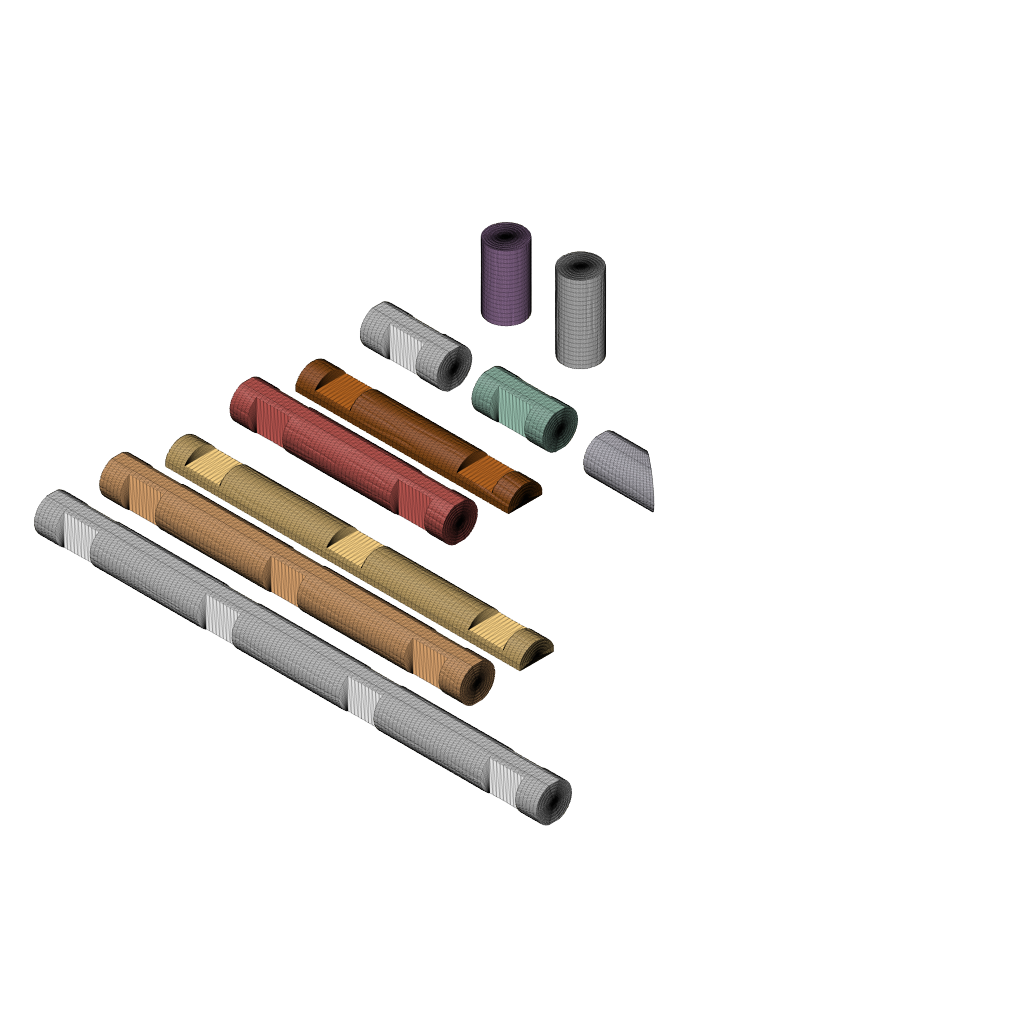
DeadPresidentTreeSections_flat_end_round (Autodesk Fusion 360 design; units mm, degrees)
part number: 2026-11-17-20-52-56-390
part number: 2026-11-17-20-52-56-571
part number: 2026-11-17-20-52-56-825
part number: 2026-11-17-20-52-57-040
part number: 2026-11-17-20-52-57-312
part number: 2026-11-17-20-52-57-710
part number: 2026-11-17-20-52-58-071
part number: 2026-11-17-20-52-58-452
part number: 2026-11-17-20-52-58-901
part number: 2026-11-17-20-52-59-269
part number: 2026-11-17-20-52-59-409
Autodesk Fusion 360 part; units mm, degrees
sketch "Section" plane through (0, 0, 0) normal (1, 0, 0) x (0, 0, -1) in component "log_1insert_1-5_8"
  circle A0 centre (-9.125, 0) radius 9.525
  dimension "d14" = 9.125
  dimension "d15" = 19.05
  constraint horizontal origin A0.centre
  measures "d14" horizontal distance of origin A0.centre
  measures "d15" diameter of A0
extrude "Log" add sketch "Section" along normal blind 41.275 makes body 1 in component "log_1insert_1-5_8"
sketch "Flats" plane through (0, 0, 0) normal (1, 0, 0) x (0, 0, -1) in component "log_1insert_1-5_8"
  line L0 (0.8, -11.525) -> (0.8, 11.525)
  line L1 (0.8, 11.525) -> (0, 11.525)
  line L2 (0, 11.525) -> (0, -11.525)
  line L3 (0, -11.525) -> (0.8, -11.525)
  line L4 (-18.25, -11.525) -> (-18.25, 11.525)
  line L5 (-18.25, 11.525) -> (-20.05, 11.525)
  line L6 (-20.05, 11.525) -> (-20.05, -11.525)
  line L7 (-20.05, -11.525) -> (-18.25, -11.525)
  dimension "d18" = 11.525
  dimension "d19" = 0.8
  dimension "d20" = 11.525
  dimension "d21" = 11.525
  dimension "d22" = 18.25
  dimension "d23" = 11.525
  dimension "d24" = 20.05
  constraint vertical L0
  constraint horizontal L1
  constraint vertical L2
  constraint horizontal L3
  constraint vertical origin L1.end
  constraint vertical L4
  constraint horizontal L5
  constraint vertical L6
  constraint horizontal L7
  measures "d18" vertical distance of origin L0.start
  measures "d19" horizontal distance of origin L0.start
  measures "d20" vertical distance of origin L1.end
  measures "d21" vertical distance of origin L4.start
  measures "d22" horizontal distance of origin L4.start
  measures "d23" vertical distance of origin L5.end
  measures "d24" horizontal distance of origin L5.end
extrude "Flats (1)" cut sketch "Flats" along normal blind 41.275 bodies 1 in component "log_1insert_1-5_8"
sketch "Notch" plane through (0, 0, 0) normal (0, 0, 1) x (1, 0, 0) in component "log_1insert_1-5_8"
  line L0 (11.3125, 4.7625) -> (29.9625, 4.7625)
  line L1 (29.9625, 4.7625) -> (29.9625, 11.525)
  line L2 (29.9625, 11.525) -> (11.3125, 11.525)
  line L3 (11.3125, 11.525) -> (11.3125, 4.7625)
  line L4 (11.3125, -4.7625) -> (29.9625, -4.7625)
  line L5 (29.9625, -4.7625) -> (29.9625, -11.525)
  line L6 (29.9625, -11.525) -> (11.3125, -11.525)
  line L7 (11.3125, -11.525) -> (11.3125, -4.7625)
  dimension "d27" = 11.3125
  dimension "d28" = 4.7625
  dimension "d29" = 29.9625
  dimension "d30" = 11.525
  dimension "d31" = 11.3125
  dimension "d32" = 4.7625
  dimension "d33" = 29.9625
  dimension "d34" = 11.525
  constraint horizontal L0
  constraint vertical L1
  constraint horizontal L2
  constraint vertical L3
  constraint horizontal L4
  constraint vertical L5
  constraint horizontal L6
  constraint vertical L7
  measures "d27" horizontal distance of origin L0.start
  measures "d28" vertical distance of origin L0.start
  measures "d29" horizontal distance of origin L1.end
  measures "d30" vertical distance of origin L1.end
  measures "d31" horizontal distance of origin L4.start
  measures "d32" vertical distance of origin L4.start
  measures "d33" horizontal distance of origin L5.end
  measures "d34" vertical distance of origin L5.end
extrude "Notch cut" cut sketch "Notch" along normal blind 21.05 bodies 1 in component "log_1insert_1-5_8"
pattern_linear "Notch pattern" count 2 spacing 0.001 along (1, 0, 0) count 3 spacing 0 along (1, 0, 0) of "Notch cut" in component "log_1insert_1-5_8"
other "Base Mesh Feature1" in component "log_1insert_1-5_8"
sketch "Section (2)" plane through (0, 0, 0) normal (1, 0, 0) x (0, 0, -1) in component "log_1insert_1-1_2_round"
  circle A0 centre (-9.125, 0) radius 9.525
  dimension "d45" = 9.125
  dimension "d46" = 19.05
  constraint horizontal origin A0.centre
  measures "d45" horizontal distance of origin A0.centre
  measures "d46" diameter of A0
extrude "Log'" add sketch "Section (2)" along normal blind 38.1 separate body makes body 2 in component "log_1insert_1-1_2_round"
sketch "Flats (2)" plane through (0, 0, 0) normal (1, 0, 0) x (0, 0, -1) in component "log_1insert_1-1_2_round"
  line L0 (0.8, -11.525) -> (0.8, 11.525)
  line L1 (0.8, 11.525) -> (0, 11.525)
  line L2 (0, 11.525) -> (0, -11.525)
  line L3 (0, -11.525) -> (0.8, -11.525)
  line L4 (-18.25, -11.525) -> (-18.25, 11.525)
  line L5 (-18.25, 11.525) -> (-20.05, 11.525)
  line L6 (-20.05, 11.525) -> (-20.05, -11.525)
  line L7 (-20.05, -11.525) -> (-18.25, -11.525)
  dimension "d49" = 11.525
  dimension "d50" = 0.8
  dimension "d51" = 11.525
  dimension "d52" = 11.525
  dimension "d53" = 18.25
  dimension "d54" = 11.525
  dimension "d55" = 20.05
  constraint vertical L0
  constraint horizontal L1
  constraint vertical L2
  constraint horizontal L3
  constraint vertical origin L1.end
  constraint vertical L4
  constraint horizontal L5
  constraint vertical L6
  constraint horizontal L7
  measures "d49" vertical distance of origin L0.start
  measures "d50" horizontal distance of origin L0.start
  measures "d51" vertical distance of origin L1.end
  measures "d52" vertical distance of origin L4.start
  measures "d53" horizontal distance of origin L4.start
  measures "d54" vertical distance of origin L5.end
  measures "d55" horizontal distance of origin L5.end
extrude "Flats (1)'" cut sketch "Flats (2)" along normal blind 38.1 bodies 2 in component "log_1insert_1-1_2_round"
sketch "Notch (2)" plane through (0, 0, 0) normal (0, 0, 1) x (1, 0, 0) in component "log_1insert_1-1_2_round"
  line L0 (9.725, 4.7625) -> (28.375, 4.7625)
  line L1 (28.375, 4.7625) -> (28.375, 11.525)
  line L2 (28.375, 11.525) -> (9.725, 11.525)
  line L3 (9.725, 11.525) -> (9.725, 4.7625)
  line L4 (9.725, -4.7625) -> (28.375, -4.7625)
  line L5 (28.375, -4.7625) -> (28.375, -11.525)
  line L6 (28.375, -11.525) -> (9.725, -11.525)
  line L7 (9.725, -11.525) -> (9.725, -4.7625)
  dimension "d58" = 9.725
  dimension "d59" = 4.7625
  dimension "d60" = 28.375
  dimension "d61" = 11.525
  dimension "d62" = 9.725
  dimension "d63" = 4.7625
  dimension "d64" = 28.375
  dimension "d65" = 11.525
  constraint horizontal L0
  constraint vertical L1
  constraint horizontal L2
  constraint vertical L3
  constraint horizontal L4
  constraint vertical L5
  constraint horizontal L6
  constraint vertical L7
  measures "d58" horizontal distance of origin L0.start
  measures "d59" vertical distance of origin L0.start
  measures "d60" horizontal distance of origin L1.end
  measures "d61" vertical distance of origin L1.end
  measures "d62" horizontal distance of origin L4.start
  measures "d63" vertical distance of origin L4.start
  measures "d64" horizontal distance of origin L5.end
  measures "d65" vertical distance of origin L5.end
extrude "Notch cut'" cut sketch "Notch (2)" along normal blind 21.05 bodies 2 in component "log_1insert_1-1_2_round"
pattern_linear "Notch pattern'" count 2 spacing 0.001 along (1, 0, 0) count 3 spacing 0 along (1, 0, 0) of "Notch cut'" in component "log_1insert_1-1_2_round"
other "Base Mesh Feature1'" in component "log_1insert_1-1_2_round"
sketch "Section (3)" plane through (0, 0, 0) normal (1, 0, 0) x (0, 0, -1) in component "log_2insert_4-1_2"
  circle A0 centre (-9.125, 0) radius 9.525
  dimension "d76" = 9.125
  dimension "d77" = 19.05
  constraint horizontal origin A0.centre
  measures "d76" horizontal distance of origin A0.centre
  measures "d77" diameter of A0
extrude "Log''" add sketch "Section (3)" along normal blind 114.3 separate body makes body 3 in component "log_2insert_4-1_2"
sketch "Flats (3)" plane through (0, 0, 0) normal (1, 0, 0) x (0, 0, -1) in component "log_2insert_4-1_2"
  line L0 (0.8, -11.525) -> (0.8, 11.525)
  line L1 (0.8, 11.525) -> (0, 11.525)
  line L2 (0, 11.525) -> (0, -11.525)
  line L3 (0, -11.525) -> (0.8, -11.525)
  line L4 (-18.25, -11.525) -> (-18.25, 11.525)
  line L5 (-18.25, 11.525) -> (-20.05, 11.525)
  line L6 (-20.05, 11.525) -> (-20.05, -11.525)
  line L7 (-20.05, -11.525) -> (-18.25, -11.525)
  dimension "d80" = 11.525
  dimension "d81" = 0.8
  dimension "d82" = 11.525
  dimension "d83" = 11.525
  dimension "d84" = 18.25
  dimension "d85" = 11.525
  dimension "d86" = 20.05
  constraint vertical L0
  constraint horizontal L1
  constraint vertical L2
  constraint horizontal L3
  constraint vertical origin L1.end
  constraint vertical L4
  constraint horizontal L5
  constraint vertical L6
  constraint horizontal L7
  measures "d80" vertical distance of origin L0.start
  measures "d81" horizontal distance of origin L0.start
  measures "d82" vertical distance of origin L1.end
  measures "d83" vertical distance of origin L4.start
  measures "d84" horizontal distance of origin L4.start
  measures "d85" vertical distance of origin L5.end
  measures "d86" horizontal distance of origin L5.end
extrude "Flats (1)''" cut sketch "Flats (3)" along normal blind 114.3 bodies 3 in component "log_2insert_4-1_2"
sketch "Notch (3)" plane through (0, 0, 0) normal (0, 0, 1) x (1, 0, 0) in component "log_2insert_4-1_2"
  line L0 (9.725, 4.7625) -> (28.375, 4.7625)
  line L1 (28.375, 4.7625) -> (28.375, 11.525)
  line L2 (28.375, 11.525) -> (9.725, 11.525)
  line L3 (9.725, 11.525) -> (9.725, 4.7625)
  line L4 (9.725, -4.7625) -> (28.375, -4.7625)
  line L5 (28.375, -4.7625) -> (28.375, -11.525)
  line L6 (28.375, -11.525) -> (9.725, -11.525)
  line L7 (9.725, -11.525) -> (9.725, -4.7625)
  dimension "d89" = 9.725
  dimension "d90" = 4.7625
  dimension "d91" = 28.375
  dimension "d92" = 11.525
  dimension "d93" = 9.725
  dimension "d94" = 4.7625
  dimension "d95" = 28.375
  dimension "d96" = 11.525
  constraint horizontal L0
  constraint vertical L1
  constraint horizontal L2
  constraint vertical L3
  constraint horizontal L4
  constraint vertical L5
  constraint horizontal L6
  constraint vertical L7
  measures "d89" horizontal distance of origin L0.start
  measures "d90" vertical distance of origin L0.start
  measures "d91" horizontal distance of origin L1.end
  measures "d92" vertical distance of origin L1.end
  measures "d93" horizontal distance of origin L4.start
  measures "d94" vertical distance of origin L4.start
  measures "d95" horizontal distance of origin L5.end
  measures "d96" vertical distance of origin L5.end
extrude "Notch cut''" cut sketch "Notch (3)" along normal blind 21.05 bodies 3 in component "log_2insert_4-1_2"
pattern_linear "Notch pattern''" count 2 spacing 76.2 along (1, 0, 0) count 3 spacing 0 along (1, 0, 0) of "Notch cut''" in component "log_2insert_4-1_2"
other "Base Mesh Feature1''" in component "log_2insert_4-1_2"
sketch "Section (4)" plane through (0, 0, 0) normal (1, 0, 0) x (0, 0, -1) in component "log_3insert_7-5_8"
  circle A0 centre (-9.125, 0) radius 9.525
  dimension "d107" = 9.125
  dimension "d108" = 19.05
  constraint horizontal origin A0.centre
  measures "d107" horizontal distance of origin A0.centre
  measures "d108" diameter of A0
extrude "Log'''" add sketch "Section (4)" along normal blind 193.675 separate body makes body 4 in component "log_3insert_7-5_8"
sketch "Flats (4)" plane through (0, 0, 0) normal (1, 0, 0) x (0, 0, -1) in component "log_3insert_7-5_8"
  line L0 (0.8, -11.525) -> (0.8, 11.525)
  line L1 (0.8, 11.525) -> (0, 11.525)
  line L2 (0, 11.525) -> (0, -11.525)
  line L3 (0, -11.525) -> (0.8, -11.525)
  line L4 (-18.25, -11.525) -> (-18.25, 11.525)
  line L5 (-18.25, 11.525) -> (-20.05, 11.525)
  line L6 (-20.05, 11.525) -> (-20.05, -11.525)
  line L7 (-20.05, -11.525) -> (-18.25, -11.525)
  dimension "d111" = 11.525
  dimension "d112" = 0.8
  dimension "d113" = 11.525
  dimension "d114" = 11.525
  dimension "d115" = 18.25
  dimension "d116" = 11.525
  dimension "d117" = 20.05
  constraint vertical L0
  constraint horizontal L1
  constraint vertical L2
  constraint horizontal L3
  constraint vertical origin L1.end
  constraint vertical L4
  constraint horizontal L5
  constraint vertical L6
  constraint horizontal L7
  measures "d111" vertical distance of origin L0.start
  measures "d112" horizontal distance of origin L0.start
  measures "d113" vertical distance of origin L1.end
  measures "d114" vertical distance of origin L4.start
  measures "d115" horizontal distance of origin L4.start
  measures "d116" vertical distance of origin L5.end
  measures "d117" horizontal distance of origin L5.end
extrude "Flats (1)'''" cut sketch "Flats (4)" along normal blind 193.675 bodies 4 in component "log_3insert_7-5_8"
sketch "Notch (4)" plane through (0, 0, 0) normal (0, 0, 1) x (1, 0, 0) in component "log_3insert_7-5_8"
  line L0 (11.3125, 4.7625) -> (29.9625, 4.7625)
  line L1 (29.9625, 4.7625) -> (29.9625, 11.525)
  line L2 (29.9625, 11.525) -> (11.3125, 11.525)
  line L3 (11.3125, 11.525) -> (11.3125, 4.7625)
  line L4 (11.3125, -4.7625) -> (29.9625, -4.7625)
  line L5 (29.9625, -4.7625) -> (29.9625, -11.525)
  line L6 (29.9625, -11.525) -> (11.3125, -11.525)
  line L7 (11.3125, -11.525) -> (11.3125, -4.7625)
  dimension "d120" = 11.3125
  dimension "d121" = 4.7625
  dimension "d122" = 29.9625
  dimension "d123" = 11.525
  dimension "d124" = 11.3125
  dimension "d125" = 4.7625
  dimension "d126" = 29.9625
  dimension "d127" = 11.525
  constraint horizontal L0
  constraint vertical L1
  constraint horizontal L2
  constraint vertical L3
  constraint horizontal L4
  constraint vertical L5
  constraint horizontal L6
  constraint vertical L7
  measures "d120" horizontal distance of origin L0.start
  measures "d121" vertical distance of origin L0.start
  measures "d122" horizontal distance of origin L1.end
  measures "d123" vertical distance of origin L1.end
  measures "d124" horizontal distance of origin L4.start
  measures "d125" vertical distance of origin L4.start
  measures "d126" horizontal distance of origin L5.end
  measures "d127" vertical distance of origin L5.end
extrude "Notch cut'''" cut sketch "Notch (4)" along normal blind 21.05 bodies 4 in component "log_3insert_7-5_8"
pattern_linear "Notch pattern'''" count 3 spacing 76.2 along (1, 0, 0) count 3 spacing 0 along (1, 0, 0) of "Notch cut'''" in component "log_3insert_7-5_8"
other "Base Mesh Feature1'''" in component "log_3insert_7-5_8"
sketch "Section (5)" plane through (0, 0, 0) normal (1, 0, 0) x (0, 0, -1) in component "log_4insert_10-5_8"
  circle A0 centre (-9.125, 0) radius 9.525
  dimension "d138" = 9.125
  dimension "d139" = 19.05
  constraint horizontal origin A0.centre
  measures "d138" horizontal distance of origin A0.centre
  measures "d139" diameter of A0
extrude "Log''''" add sketch "Section (5)" along normal blind 269.875 separate body makes body 5 in component "log_4insert_10-5_8"
sketch "Flats (5)" plane through (0, 0, 0) normal (1, 0, 0) x (0, 0, -1) in component "log_4insert_10-5_8"
  line L0 (0.8, -11.525) -> (0.8, 11.525)
  line L1 (0.8, 11.525) -> (0, 11.525)
  line L2 (0, 11.525) -> (0, -11.525)
  line L3 (0, -11.525) -> (0.8, -11.525)
  line L4 (-18.25, -11.525) -> (-18.25, 11.525)
  line L5 (-18.25, 11.525) -> (-20.05, 11.525)
  line L6 (-20.05, 11.525) -> (-20.05, -11.525)
  line L7 (-20.05, -11.525) -> (-18.25, -11.525)
  dimension "d142" = 11.525
  dimension "d143" = 0.8
  dimension "d144" = 11.525
  dimension "d145" = 11.525
  dimension "d146" = 18.25
  dimension "d147" = 11.525
  dimension "d148" = 20.05
  constraint vertical L0
  constraint horizontal L1
  constraint vertical L2
  constraint horizontal L3
  constraint vertical origin L1.end
  constraint vertical L4
  constraint horizontal L5
  constraint vertical L6
  constraint horizontal L7
  measures "d142" vertical distance of origin L0.start
  measures "d143" horizontal distance of origin L0.start
  measures "d144" vertical distance of origin L1.end
  measures "d145" vertical distance of origin L4.start
  measures "d146" horizontal distance of origin L4.start
  measures "d147" vertical distance of origin L5.end
  measures "d148" horizontal distance of origin L5.end
extrude "Flats (1)''''" cut sketch "Flats (5)" along normal blind 269.875 bodies 5 in component "log_4insert_10-5_8"
sketch "Notch (5)" plane through (0, 0, 0) normal (0, 0, 1) x (1, 0, 0) in component "log_4insert_10-5_8"
  line L0 (11.3125, 4.7625) -> (29.9625, 4.7625)
  line L1 (29.9625, 4.7625) -> (29.9625, 11.525)
  line L2 (29.9625, 11.525) -> (11.3125, 11.525)
  line L3 (11.3125, 11.525) -> (11.3125, 4.7625)
  line L4 (11.3125, -4.7625) -> (29.9625, -4.7625)
  line L5 (29.9625, -4.7625) -> (29.9625, -11.525)
  line L6 (29.9625, -11.525) -> (11.3125, -11.525)
  line L7 (11.3125, -11.525) -> (11.3125, -4.7625)
  dimension "d151" = 11.3125
  dimension "d152" = 4.7625
  dimension "d153" = 29.9625
  dimension "d154" = 11.525
  dimension "d155" = 11.3125
  dimension "d156" = 4.7625
  dimension "d157" = 29.9625
  dimension "d158" = 11.525
  constraint horizontal L0
  constraint vertical L1
  constraint horizontal L2
  constraint vertical L3
  constraint horizontal L4
  constraint vertical L5
  constraint horizontal L6
  constraint vertical L7
  measures "d151" horizontal distance of origin L0.start
  measures "d152" vertical distance of origin L0.start
  measures "d153" horizontal distance of origin L1.end
  measures "d154" vertical distance of origin L1.end
  measures "d155" horizontal distance of origin L4.start
  measures "d156" vertical distance of origin L4.start
  measures "d157" horizontal distance of origin L5.end
  measures "d158" vertical distance of origin L5.end
extrude "Notch cut''''" cut sketch "Notch (5)" along normal blind 21.05 bodies 5 in component "log_4insert_10-5_8"
pattern_linear "Notch pattern''''" count 4 spacing 76.2 along (1, 0, 0) count 3 spacing 0 along (1, 0, 0) of "Notch cut''''" in component "log_4insert_10-5_8"
other "Base Mesh Feature1''''" in component "log_4insert_10-5_8"
sketch "Section (6)" plane through (0, 0, 0) normal (1, 0, 0) x (0, 0, -1) in component "base_log_4-1_2"
  circle A0 centre (0, 0) radius 9.525
  dimension "d169" = 19.05
  constraint coincident A0.centre origin
  measures "d169" diameter of A0
extrude "Log'''''" add sketch "Section (6)" along normal blind 114.3 separate body makes body 6 in component "base_log_4-1_2"
sketch "Bed and side flats" plane through (0, 0, 0) normal (1, 0, 0) x (0, 0, -1) in component "base_log_4-1_2"
  line L0 (10.525, -11.525) -> (10.525, 11.525)
  line L1 (10.525, 11.525) -> (0, 11.525)
  line L2 (0, 11.525) -> (0, -11.525)
  line L3 (0, -11.525) -> (10.525, -11.525)
  line L4 (1, 9.125) -> (1, 11.525)
  line L5 (1, 11.525) -> (-20.05, 11.525)
  line L6 (-20.05, 11.525) -> (-20.05, 9.125)
  line L7 (-20.05, 9.125) -> (1, 9.125)
  line L8 (1, -9.125) -> (1, -11.525)
  line L9 (1, -11.525) -> (-20.05, -11.525)
  line L10 (-20.05, -11.525) -> (-20.05, -9.125)
  line L11 (-20.05, -9.125) -> (1, -9.125)
  dimension "d172" = 11.525
  dimension "d173" = 10.525
  dimension "d174" = 11.525
  dimension "d175" = 9.125
  dimension "d176" = 1
  dimension "d177" = 11.525
  dimension "d178" = 20.05
  dimension "d179" = 9.125
  dimension "d180" = 1
  dimension "d181" = 11.525
  dimension "d182" = 20.05
  constraint vertical L0
  constraint horizontal L1
  constraint vertical L2
  constraint horizontal L3
  constraint vertical origin L1.end
  constraint vertical L4
  constraint horizontal L5
  constraint vertical L6
  constraint horizontal L7
  constraint vertical L8
  constraint horizontal L9
  constraint vertical L10
  constraint horizontal L11
  measures "d172" vertical distance of origin L0.start
  measures "d173" horizontal distance of origin L0.start
  measures "d174" vertical distance of origin L1.end
  measures "d175" vertical distance of origin L4.start
  measures "d176" horizontal distance of origin L4.start
  measures "d177" vertical distance of origin L5.end
  measures "d178" horizontal distance of origin L5.end
  measures "d179" vertical distance of origin L8.start
  measures "d180" horizontal distance of origin L8.start
  measures "d181" vertical distance of origin L9.end
  measures "d182" horizontal distance of origin L9.end
extrude "Bed and side flats (1)" cut sketch "Bed and side flats" along normal blind 114.3 bodies 6 in component "base_log_4-1_2"
sketch "Notch (6)" plane through (0, 0, 0) normal (0, 1, 0) x (1, 0, 0) in component "base_log_4-1_2"
  line L0 (9.725, -4.7625) -> (28.375, -4.7625)
  line L1 (28.375, -4.7625) -> (28.375, -10.525)
  line L2 (28.375, -10.525) -> (9.725, -10.525)
  line L3 (9.725, -10.525) -> (9.725, -4.7625)
  dimension "d185" = 9.725
  dimension "d186" = 4.7625
  dimension "d187" = 28.375
  dimension "d188" = 10.525
  constraint horizontal L0
  constraint vertical L1
  constraint horizontal L2
  constraint vertical L3
  measures "d185" horizontal distance of origin L0.start
  measures "d186" vertical distance of origin L0.start
  measures "d187" horizontal distance of origin L1.end
  measures "d188" vertical distance of origin L1.end
extrude "Notch cut'''''" cut sketch "Notch (6)" along normal mid plane 21.05 bodies 6 in component "base_log_4-1_2"
pattern_linear "Notch pattern'''''" count 2 spacing 76.2 along (1, 0, 0) count 3 spacing 0 along (1, 0, 0) of "Notch cut'''''" in component "base_log_4-1_2"
other "Base Mesh Feature1'''''" in component "base_log_4-1_2"
sketch "Section (7)" plane through (0, 0, 0) normal (1, 0, 0) x (0, 0, -1) in component "base_log_7-1_2"
  circle A0 centre (0, 0) radius 9.525
  dimension "d199" = 19.05
  constraint coincident A0.centre origin
  measures "d199" diameter of A0
extrude "Log''''''" add sketch "Section (7)" along normal blind 190.5 separate body makes body 7 in component "base_log_7-1_2"
sketch "Bed and side flats (2)" plane through (0, 0, 0) normal (1, 0, 0) x (0, 0, -1) in component "base_log_7-1_2"
  line L0 (10.525, -11.525) -> (10.525, 11.525)
  line L1 (10.525, 11.525) -> (0, 11.525)
  line L2 (0, 11.525) -> (0, -11.525)
  line L3 (0, -11.525) -> (10.525, -11.525)
  line L4 (1, 9.125) -> (1, 11.525)
  line L5 (1, 11.525) -> (-20.05, 11.525)
  line L6 (-20.05, 11.525) -> (-20.05, 9.125)
  line L7 (-20.05, 9.125) -> (1, 9.125)
  line L8 (1, -9.125) -> (1, -11.525)
  line L9 (1, -11.525) -> (-20.05, -11.525)
  line L10 (-20.05, -11.525) -> (-20.05, -9.125)
  line L11 (-20.05, -9.125) -> (1, -9.125)
  dimension "d202" = 11.525
  dimension "d203" = 10.525
  dimension "d204" = 11.525
  dimension "d205" = 9.125
  dimension "d206" = 1
  dimension "d207" = 11.525
  dimension "d208" = 20.05
  dimension "d209" = 9.125
  dimension "d210" = 1
  dimension "d211" = 11.525
  dimension "d212" = 20.05
  constraint vertical L0
  constraint horizontal L1
  constraint vertical L2
  constraint horizontal L3
  constraint vertical origin L1.end
  constraint vertical L4
  constraint horizontal L5
  constraint vertical L6
  constraint horizontal L7
  constraint vertical L8
  constraint horizontal L9
  constraint vertical L10
  constraint horizontal L11
  measures "d202" vertical distance of origin L0.start
  measures "d203" horizontal distance of origin L0.start
  measures "d204" vertical distance of origin L1.end
  measures "d205" vertical distance of origin L4.start
  measures "d206" horizontal distance of origin L4.start
  measures "d207" vertical distance of origin L5.end
  measures "d208" horizontal distance of origin L5.end
  measures "d209" vertical distance of origin L8.start
  measures "d210" horizontal distance of origin L8.start
  measures "d211" vertical distance of origin L9.end
  measures "d212" horizontal distance of origin L9.end
extrude "Bed and side flats (1)'" cut sketch "Bed and side flats (2)" along normal blind 190.5 bodies 7 in component "base_log_7-1_2"
sketch "Notch (7)" plane through (0, 0, 0) normal (0, 1, 0) x (1, 0, 0) in component "base_log_7-1_2"
  line L0 (9.725, -4.7625) -> (28.375, -4.7625)
  line L1 (28.375, -4.7625) -> (28.375, -10.525)
  line L2 (28.375, -10.525) -> (9.725, -10.525)
  line L3 (9.725, -10.525) -> (9.725, -4.7625)
  dimension "d215" = 9.725
  dimension "d216" = 4.7625
  dimension "d217" = 28.375
  dimension "d218" = 10.525
  constraint horizontal L0
  constraint vertical L1
  constraint horizontal L2
  constraint vertical L3
  measures "d215" horizontal distance of origin L0.start
  measures "d216" vertical distance of origin L0.start
  measures "d217" horizontal distance of origin L1.end
  measures "d218" vertical distance of origin L1.end
extrude "Notch cut''''''" cut sketch "Notch (7)" along normal mid plane 21.05 bodies 7 in component "base_log_7-1_2"
pattern_linear "Notch pattern''''''" count 3 spacing 76.2 along (1, 0, 0) count 3 spacing 0 along (1, 0, 0) of "Notch cut''''''" in component "base_log_7-1_2"
other "Base Mesh Feature1''''''" in component "base_log_7-1_2"
sketch "Section (8)" plane through (0, 0, 0) normal (1, 0, 0) x (0, 0, -1) in component "beveled_end_1-1_2"
  circle A0 centre (-9.125, 0) radius 9.525
  dimension "d227" = 9.125
  dimension "d228" = 19.05
  constraint horizontal origin A0.centre
  measures "d227" horizontal distance of origin A0.centre
  measures "d228" diameter of A0
extrude "Log'''''''" add sketch "Section (8)" along normal blind 38.1 separate body makes body 8 in component "beveled_end_1-1_2"
sketch "Flats (6)" plane through (0, 0, 0) normal (1, 0, 0) x (0, 0, -1) in component "beveled_end_1-1_2"
  line L0 (0.8, -11.525) -> (0.8, 11.525)
  line L1 (0.8, 11.525) -> (0, 11.525)
  line L2 (0, 11.525) -> (0, -11.525)
  line L3 (0, -11.525) -> (0.8, -11.525)
  line L4 (-18.25, -11.525) -> (-18.25, 11.525)
  line L5 (-18.25, 11.525) -> (-20.05, 11.525)
  line L6 (-20.05, 11.525) -> (-20.05, -11.525)
  line L7 (-20.05, -11.525) -> (-18.25, -11.525)
  dimension "d231" = 11.525
  dimension "d232" = 0.8
  dimension "d233" = 11.525
  dimension "d234" = 11.525
  dimension "d235" = 18.25
  dimension "d236" = 11.525
  dimension "d237" = 20.05
  constraint vertical L0
  constraint horizontal L1
  constraint vertical L2
  constraint horizontal L3
  constraint vertical origin L1.end
  constraint vertical L4
  constraint horizontal L5
  constraint vertical L6
  constraint horizontal L7
  measures "d231" vertical distance of origin L0.start
  measures "d232" horizontal distance of origin L0.start
  measures "d233" vertical distance of origin L1.end
  measures "d234" vertical distance of origin L4.start
  measures "d235" horizontal distance of origin L4.start
  measures "d236" vertical distance of origin L5.end
  measures "d237" horizontal distance of origin L5.end
extrude "Flats (1)'''''" cut sketch "Flats (6)" along normal blind 38.1 bodies 8 in component "beveled_end_1-1_2"
sketch "Slant" plane through (0, 0, 0) normal (0, 0, 1) x (1, 0, 0) in component "beveled_end_1-1_2"
  line L0 (38.1, -9.525) -> (38.1, 9.525)
  line L1 (38.1, 9.525) -> (14.5752, 9.525)
  line L2 (14.5752, 9.525) -> (38.1, -9.525)
  dimension "d240" = 38.1
  dimension "d241" = 9.525
  dimension "d242" = 9.525
  dimension "d243" = 14.5752
  constraint vertical L0.start L0.end
  constraint horizontal L0.end L1.end
  measures "d240" horizontal distance of origin L0.start
  measures "d241" vertical distance of origin L0.start
  measures "d242" vertical distance of origin L0.end
  measures "d243" horizontal distance of origin L1.end
extrude "Slanted end" cut sketch "Slant" along normal blind 21.05 bodies 8 in component "beveled_end_1-1_2"
other "Base Mesh Feature1'''''''" in component "beveled_end_1-1_2"
sketch "Section (9)" plane through (0, 0, 0) normal (0, 0, 1) x (1, 0, 0) in component "solid_log_1-3_8"
  circle A0 centre (9.525, 9.525) radius 9.525
  dimension "d247" = 9.525
  dimension "d248" = 9.525
  dimension "d249" = 19.05
  measures "d247" horizontal distance of origin A0.centre
  measures "d248" vertical distance of origin A0.centre
  measures "d249" diameter of A0
extrude "Log''''''''" add sketch "Section (9)" along normal blind 34.925 separate body makes body 9 in component "solid_log_1-3_8"
other "Base Mesh Feature1''''''''" in component "solid_log_1-3_8"
sketch "Section (10)" plane through (0, 0, 0) normal (0, 0, 1) x (1, 0, 0) in component "solid_log_1-5_8"
  circle A0 centre (9.525, 9.525) radius 9.525
  dimension "d253" = 9.525
  dimension "d254" = 9.525
  dimension "d255" = 19.05
  measures "d253" horizontal distance of origin A0.centre
  measures "d254" vertical distance of origin A0.centre
  measures "d255" diameter of A0
extrude "Log'''''''''" add sketch "Section (10)" along normal blind 41.275 separate body makes body 10 in component "solid_log_1-5_8"
other "Base Mesh Feature1'''''''''" in component "solid_log_1-5_8"
component "log_1insert_1-5_8" placed x (1, 0, 0) y (0, 1, 0) z (0, 0, 1) at (0, 175, 0)
component "log_1insert_1-1_2_round" placed x (1, 0, 0) y (0, 1, 0) z (0, 0, 1) at (60, 175, 0)
component "log_2insert_4-1_2" placed x (1, 0, 0) y (0, 1, 0) z (0, 0, 1) at (0, 105, 0)
component "log_3insert_7-5_8" placed x (1, 0, 0) y (0, 1, 0) z (0, 0, 1) at (0, 35, 0)
component "log_4insert_10-5_8" placed x (1, 0, 0) y (0, 1, 0) z (0, 0, 1) at (0, 0, 0)
component "base_log_4-1_2" placed x (1, 0, 0) y (0, 1, 0) z (0, 0, 1) at (0, 140, 0)
component "base_log_7-1_2" placed x (1, 0, 0) y (0, 1, 0) z (0, 0, 1) at (0, 70, 0)
component "beveled_end_1-1_2" placed x (1, 0, 0) y (0, 1, 0) z (0, 0, 1) at (120, 175, 0)
component "solid_log_1-3_8" placed x (1, 0, 0) y (0, 1, 0) z (0, 0, 1) at (10, 215, 0)
component "solid_log_1-5_8" placed x (1, 0, 0) y (0, 1, 0) z (0, 0, 1) at (50, 215, 0)
hidden bodies 1 2 3 4 5 6 7 8 9 10
equation "LogDia = 0.75 in" comment "Log diameter (across the flats of an octagonal log)"
equation "NotchDepth = 0.1875 in" comment "Notch depth, each side of a log"
equation "NotchCenters = 3 in" comment "Spacing between notch centres"
equation "Clearance = 0.2 mm" comment "Fit clearance per side. Try 0.3 mm for PETG"
equation "PrintFlat = 0.8 mm" comment "Total width taken off a log, as an equal flat on each side; one is the bed side"
equation "MateWidth = LogDia - PrintFlat" comment "Width of a log, base log or gable where it sits in a notch"
equation "NotchWidth = MateWidth + 2 * Clearance" comment "Notch width (mating width plus clearance on each side)"
equation "CourseRise = LogDia - 2 * NotchDepth" comment "Height gained per crossing course"
equation "BaseLogHeight = LogDia / 2" comment "Base-log height (a log split in half along its axis)"
equation "L1a_Length = 1.625 in" comment "Overall length"
equation "L1a_Notches = 1" comment "Number of notch positions"
equation "L1a_FirstNotch = ( L1a_Length - ( L1a_Notches - 1 ) * NotchCenters ) / 2" comment "Centre of the first notch (keeps the row of notches centred)"
equation "L1a_NotchStep = NotchCenters * min(1; L1a_Notches - 1) + 0.001 mm * ( 1 - min(1; L1a_Notches - 1) )" comment "Pattern step: NotchCenters, or about zero when there is only one notch"
equation "d14 = LogDia / 2 - PrintFlat / 2"
equation "d15 = LogDia"
equation "d16 = L1a_Length"
equation "d18 = LogDia / 2 + 2 mm"
equation "d19 = PrintFlat"
equation "d20 = LogDia / 2 + 2 mm"
equation "d21 = LogDia / 2 + 2 mm"
equation "d22 = MateWidth"
equation "d23 = LogDia / 2 + 2 mm"
equation "d24 = LogDia + 1 mm"
equation "d25 = L1a_Length"
equation "d27 = L1a_FirstNotch - NotchWidth / 2"
equation "d28 = LogDia / 2 - NotchDepth"
equation "d29 = L1a_FirstNotch + NotchWidth / 2"
equation "d30 = LogDia / 2 + 2 mm"
equation "d31 = L1a_FirstNotch - NotchWidth / 2"
equation "d32 = LogDia / 2 - NotchDepth"
equation "d33 = L1a_FirstNotch + NotchWidth / 2"
equation "d34 = LogDia / 2 + 2 mm"
equation "d35 = LogDia + 2 mm"
equation "d37 = max(L1a_Notches; 2)"
equation "d39 = L1a_NotchStep"
equation "L1b_Length = 1.5 in" comment "Overall length"
equation "L1b_Notches = 1" comment "Number of notch positions"
equation "L1b_FirstNotch = ( L1b_Length - ( L1b_Notches - 1 ) * NotchCenters ) / 2" comment "Centre of the first notch (keeps the row of notches centred)"
equation "L1b_NotchStep = NotchCenters * min(1; L1b_Notches - 1) + 0.001 mm * ( 1 - min(1; L1b_Notches - 1) )" comment "Pattern step: NotchCenters, or about zero when there is only one notch"
equation "d45 = LogDia / 2 - PrintFlat / 2"
equation "d46 = LogDia"
equation "d47 = L1b_Length"
equation "d49 = LogDia / 2 + 2 mm"
equation "d50 = PrintFlat"
equation "d51 = LogDia / 2 + 2 mm"
equation "d52 = LogDia / 2 + 2 mm"
equation "d53 = MateWidth"
equation "d54 = LogDia / 2 + 2 mm"
equation "d55 = LogDia + 1 mm"
equation "d56 = L1b_Length"
equation "d58 = L1b_FirstNotch - NotchWidth / 2"
equation "d59 = LogDia / 2 - NotchDepth"
equation "d60 = L1b_FirstNotch + NotchWidth / 2"
equation "d61 = LogDia / 2 + 2 mm"
equation "d62 = L1b_FirstNotch - NotchWidth / 2"
equation "d63 = LogDia / 2 - NotchDepth"
equation "d64 = L1b_FirstNotch + NotchWidth / 2"
equation "d65 = LogDia / 2 + 2 mm"
equation "d66 = LogDia + 2 mm"
equation "d68 = max(L1b_Notches; 2)"
equation "d70 = L1b_NotchStep"
equation "L2_Length = 4.5 in" comment "Overall length"
equation "L2_Notches = 2" comment "Number of notch positions"
equation "L2_FirstNotch = ( L2_Length - ( L2_Notches - 1 ) * NotchCenters ) / 2" comment "Centre of the first notch (keeps the row of notches centred)"
equation "L2_NotchStep = NotchCenters * min(1; L2_Notches - 1) + 0.001 mm * ( 1 - min(1; L2_Notches - 1) )" comment "Pattern step: NotchCenters, or about zero when there is only one notch"
equation "d76 = LogDia / 2 - PrintFlat / 2"
equation "d77 = LogDia"
equation "d78 = L2_Length"
equation "d80 = LogDia / 2 + 2 mm"
equation "d81 = PrintFlat"
equation "d82 = LogDia / 2 + 2 mm"
equation "d83 = LogDia / 2 + 2 mm"
equation "d84 = MateWidth"
equation "d85 = LogDia / 2 + 2 mm"
equation "d86 = LogDia + 1 mm"
equation "d87 = L2_Length"
equation "d89 = L2_FirstNotch - NotchWidth / 2"
equation "d90 = LogDia / 2 - NotchDepth"
equation "d91 = L2_FirstNotch + NotchWidth / 2"
equation "d92 = LogDia / 2 + 2 mm"
equation "d93 = L2_FirstNotch - NotchWidth / 2"
equation "d94 = LogDia / 2 - NotchDepth"
equation "d95 = L2_FirstNotch + NotchWidth / 2"
equation "d96 = LogDia / 2 + 2 mm"
equation "d97 = LogDia + 2 mm"
equation "d99 = max(L2_Notches; 2)"
equation "d101 = L2_NotchStep"
equation "L3_Length = 7.625 in" comment "Overall length"
equation "L3_Notches = 3" comment "Number of notch positions"
equation "L3_FirstNotch = ( L3_Length - ( L3_Notches - 1 ) * NotchCenters ) / 2" comment "Centre of the first notch (keeps the row of notches centred)"
equation "L3_NotchStep = NotchCenters * min(1; L3_Notches - 1) + 0.001 mm * ( 1 - min(1; L3_Notches - 1) )" comment "Pattern step: NotchCenters, or about zero when there is only one notch"
equation "d107 = LogDia / 2 - PrintFlat / 2"
equation "d108 = LogDia"
equation "d109 = L3_Length"
equation "d111 = LogDia / 2 + 2 mm"
equation "d112 = PrintFlat"
equation "d113 = LogDia / 2 + 2 mm"
equation "d114 = LogDia / 2 + 2 mm"
equation "d115 = MateWidth"
equation "d116 = LogDia / 2 + 2 mm"
equation "d117 = LogDia + 1 mm"
equation "d118 = L3_Length"
equation "d120 = L3_FirstNotch - NotchWidth / 2"
equation "d121 = LogDia / 2 - NotchDepth"
equation "d122 = L3_FirstNotch + NotchWidth / 2"
equation "d123 = LogDia / 2 + 2 mm"
equation "d124 = L3_FirstNotch - NotchWidth / 2"
equation "d125 = LogDia / 2 - NotchDepth"
equation "d126 = L3_FirstNotch + NotchWidth / 2"
equation "d127 = LogDia / 2 + 2 mm"
equation "d128 = LogDia + 2 mm"
equation "d130 = max(L3_Notches; 2)"
equation "d132 = L3_NotchStep"
equation "L4_Length = 10.625 in" comment "Overall length"
equation "L4_Notches = 4" comment "Number of notch positions"
equation "L4_FirstNotch = ( L4_Length - ( L4_Notches - 1 ) * NotchCenters ) / 2" comment "Centre of the first notch (keeps the row of notches centred)"
equation "L4_NotchStep = NotchCenters * min(1; L4_Notches - 1) + 0.001 mm * ( 1 - min(1; L4_Notches - 1) )" comment "Pattern step: NotchCenters, or about zero when there is only one notch"
equation "d138 = LogDia / 2 - PrintFlat / 2"
equation "d139 = LogDia"
equation "d140 = L4_Length"
equation "d142 = LogDia / 2 + 2 mm"
equation "d143 = PrintFlat"
equation "d144 = LogDia / 2 + 2 mm"
equation "d145 = LogDia / 2 + 2 mm"
equation "d146 = MateWidth"
equation "d147 = LogDia / 2 + 2 mm"
equation "d148 = LogDia + 1 mm"
equation "d149 = L4_Length"
equation "d151 = L4_FirstNotch - NotchWidth / 2"
equation "d152 = LogDia / 2 - NotchDepth"
equation "d153 = L4_FirstNotch + NotchWidth / 2"
equation "d154 = LogDia / 2 + 2 mm"
equation "d155 = L4_FirstNotch - NotchWidth / 2"
equation "d156 = LogDia / 2 - NotchDepth"
equation "d157 = L4_FirstNotch + NotchWidth / 2"
equation "d158 = LogDia / 2 + 2 mm"
equation "d159 = LogDia + 2 mm"
equation "d161 = max(L4_Notches; 2)"
equation "d163 = L4_NotchStep"
equation "Half2_Length = 4.5 in" comment "Overall length"
equation "Half2_Notches = 2" comment "Number of notch positions"
equation "Half2_FirstNotch = ( Half2_Length - ( Half2_Notches - 1 ) * NotchCenters ) / 2" comment "Centre of the first notch (keeps the row of notches centred)"
equation "Half2_NotchStep = NotchCenters * min(1; Half2_Notches - 1) + 0.001 mm * ( 1 - min(1; Half2_Notches - 1) )" comment "Pattern step: NotchCenters, or about zero when there is only one notch"
equation "d169 = LogDia"
equation "d170 = Half2_Length"
equation "d172 = LogDia / 2 + 2 mm"
equation "d173 = LogDia / 2 + 1 mm"
equation "d174 = LogDia / 2 + 2 mm"
equation "d175 = MateWidth / 2"
equation "d177 = LogDia / 2 + 2 mm"
equation "d178 = LogDia + 1 mm"
equation "d179 = MateWidth / 2"
equation "d181 = LogDia / 2 + 2 mm"
equation "d182 = LogDia + 1 mm"
equation "d183 = Half2_Length"
equation "d185 = Half2_FirstNotch - NotchWidth / 2"
equation "d186 = BaseLogHeight - NotchDepth"
equation "d187 = Half2_FirstNotch + NotchWidth / 2"
equation "d188 = BaseLogHeight + 1 mm"
equation "d189 = LogDia + 2 mm"
equation "d191 = max(Half2_Notches; 2)"
equation "d193 = Half2_NotchStep"
equation "Half3_Length = 7.5 in" comment "Overall length"
equation "Half3_Notches = 3" comment "Number of notch positions"
equation "Half3_FirstNotch = ( Half3_Length - ( Half3_Notches - 1 ) * NotchCenters ) / 2" comment "Centre of the first notch (keeps the row of notches centred)"
equation "Half3_NotchStep = NotchCenters * min(1; Half3_Notches - 1) + 0.001 mm * ( 1 - min(1; Half3_Notches - 1) )" comment "Pattern step: NotchCenters, or about zero when there is only one notch"
equation "d199 = LogDia"
equation "d200 = Half3_Length"
equation "d202 = LogDia / 2 + 2 mm"
equation "d203 = LogDia / 2 + 1 mm"
equation "d204 = LogDia / 2 + 2 mm"
equation "d205 = MateWidth / 2"
equation "d207 = LogDia / 2 + 2 mm"
equation "d208 = LogDia + 1 mm"
equation "d209 = MateWidth / 2"
equation "d211 = LogDia / 2 + 2 mm"
equation "d212 = LogDia + 1 mm"
equation "d213 = Half3_Length"
equation "d215 = Half3_FirstNotch - NotchWidth / 2"
equation "d216 = BaseLogHeight - NotchDepth"
equation "d217 = Half3_FirstNotch + NotchWidth / 2"
equation "d218 = BaseLogHeight + 1 mm"
equation "d219 = LogDia + 2 mm"
equation "d221 = max(Half3_Notches; 2)"
equation "d223 = Half3_NotchStep"
equation "Bev_Length = 1.5 in" comment "Length along the long edge"
equation "Bev_Angle = 39 deg" comment "Angle of the slanted end (roof pitch of the wooden triangle)"
equation "d227 = LogDia / 2 - PrintFlat / 2"
equation "d228 = LogDia"
equation "d229 = Bev_Length"
equation "d231 = LogDia / 2 + 2 mm"
equation "d232 = PrintFlat"
equation "d233 = LogDia / 2 + 2 mm"
equation "d234 = LogDia / 2 + 2 mm"
equation "d235 = MateWidth"
equation "d236 = LogDia / 2 + 2 mm"
equation "d237 = LogDia + 1 mm"
equation "d238 = Bev_Length"
equation "d240 = Bev_Length"
equation "d241 = LogDia / 2"
equation "d242 = LogDia / 2"
equation "d243 = Bev_Length - LogDia / tan(Bev_Angle)"
equation "d244 = LogDia + 2 mm"
equation "Solid1_Length = 1.375 in" comment "Length"
equation "d247 = LogDia / 2"
equation "d248 = LogDia / 2"
equation "d249 = LogDia"
equation "d250 = Solid1_Length"
equation "Solid2_Length = 1.625 in" comment "Length"
equation "d253 = LogDia / 2"
equation "d254 = LogDia / 2"
equation "d255 = LogDia"
equation "d256 = Solid2_Length"
named bodies: "log_1insert_1-5_8", "log_1insert_1-1_2_round", "log_2insert_4-1_2", "log_3insert_7-5_8", "log_4insert_10-5_8", "base_log_4-1_2", "base_log_7-1_2", "beveled_end_1-1_2", "solid_log_1-3_8", "solid_log_1-5_8"
